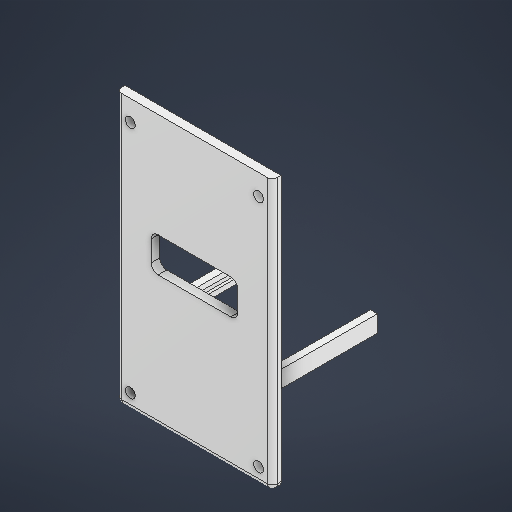
# Autodesk Inventor part: Крышка_голова_передняя
Saved by Autodesk Inventor 2026 (Build 300175050, 175E)
## iProperties
Created: 2026-10-25
Part Number: Крышка_голова_передняя
Material: Пластик АБС
Document SubType Name: Modeling
Designer: VK7
Density: 1.06 g/cm^3
Appearance: Гладкий — белый
Author: VK7
Autodesk Inventor part; units mm, degrees
ref_plane "YZ Plane" through (0, 0, 0) normal (1, 0, 0) x (0, 1, 0)
ref_plane "XZ Plane" through (0, 0, 0) normal (0, 1, 0) x (-1, 0, 0)
sketch "Эскиз1" plane through (0, 0, 0) normal (0, 0, 1) x (1, 0, 0)
  line L0 (0, 0) -> (45, 0)
  line L1 (45, 0) -> (45, 78)
  line L2 (45, 78) -> (0, 78)
  line L3 (0, 78) -> (0, 0)
  dimension "d0" = 45
  dimension "d1" = 78
  constraints: 8 end point, 2 parallel, 1 horizontal, 1 perpendicular
  measures "d0" distance of L2.end L1.end
  measures "d1" distance of L1.end L0.end
extrude "Выдавливание1" add sketch "Эскиз1" along normal blind 2.5
sketch "Эскиз2" plane through (0, 0, 2.5) normal (0, 0, 1) x (1, 0, 0)
  line L0 (0, 0) -> (4, 0)
  line L1 (0, 0) -> (45, 0) projected
  line L2 (4, 0) -> (4, 4.45)
  circle A0 centre (4, 4.45) radius 1.4
  line L3 (22.5, 0) -> (22.5, 4.5)
  circle A1 centre (41, 4.45) radius 1.4
  line L4 (4, 4.45) -> (4, 38.225)
  line L5 (4, 38.225) -> (6, 38.225)
  circle A2 centre (4, 72) radius 1.4
  circle A3 centre (41, 72) radius 1.4
  dimension "d4" = 4
  dimension "d5" = 4.45
  dimension "d6" = 2.8
  dimension "d36" = 33.775
  dimension "d37" = 2
  constraints: 10 end point, 4 centre point, 3 symmetric about line, 2 perpendicular, 2 vertical, 1 coincident, 1 midpoint, 1 point on line, 3 other
  measures "d4" distance of L0.start L0.end
  measures "d5" distance of L0.end L2.end
  measures "d6" diameter of A0
  measures "d36" distance of L4.start L4.end
  measures "d37" distance of L4.end L5.end
extrude "Выдавливание2" cut sketch "Эскиз2" against normal blind 2.5
ref_plane "РабПлоскость1" through (0, 21, 0) normal (0, -1, 0) x (1, 0, 0)
fillet "Сопряжение4" radius 1.5 3 edges at (0, 39, 2.5) (45, 39, 2.5) (22.5, 0, 2.5)
fillet "Сопряжение5" radius 1.5 4 edges at (44.5607, 0.4393, 2.0607) (45, 0, 0.5) (0, 0, 0.5) (0.4393, 0.4393, 2.0607)
sketch "Эскиз4" plane through (0, 0, 0) normal (0, 0, -1) x (-1, 0, 0)
  line L0 (-1.5, 0) -> (-43.5, 0) projected
  line L1 (-22.5, 0) -> (-22.5, 21)
  line L2 (-22.5, 21) -> (-22.5, 21.925)
  line L3 (-22.5, 21.925) -> (-38.6, 21.925)
  line L4 (-38.6, 21.925) -> (-38.6, 21)
  line L5 (-38.6, 21) -> (-37.8, 21)
  line L6 (-37.8, 21) -> (-37.8, 19.5)
  line L7 (-37.8, 19.5) -> (-39.8, 19.5)
  line L8 (-39.8, 19.5) -> (-39.8, 21.925)
  line L9 (-38.6, 21.925) -> (-38.6, 22.85)
  line L10 (-38.6, 22.85) -> (-37.8, 22.85)
  line L11 (-37.8, 22.85) -> (-37.8, 24.35)
  line L12 (-37.8, 24.35) -> (-39.8, 24.35)
  line L13 (-39.8, 24.35) -> (-39.8, 21.925)
  line L14 (-6.4, 21.925) -> (-6.4, 21)
  line L15 (-6.4, 21) -> (-7.2, 21)
  line L16 (-7.2, 21) -> (-7.2, 19.5)
  line L17 (-7.2, 19.5) -> (-5.2, 19.5)
  line L18 (-5.2, 19.5) -> (-5.2, 21.925)
  line L19 (-5.2, 24.35) -> (-5.2, 21.925)
  line L20 (-7.2, 24.35) -> (-5.2, 24.35)
  line L21 (-7.2, 22.85) -> (-7.2, 24.35)
  line L22 (-6.4, 22.85) -> (-7.2, 22.85)
  line L23 (-6.4, 21.925) -> (-6.4, 22.85)
  point P0 (0, 0)
  dimension "d27" = 21
  dimension "d28" = 0.925
  dimension "d29" = 16.1
  dimension "d30" = 0.8
  dimension "d31" = 1.5
  dimension "d32" = 2
  constraints: 46 end point, 14 symmetric about line, 5 perpendicular, 1 horizontal, 1 midpoint, 1 point on line, 1 vertical
  measures "d27" distance of L1.start L1.end
  measures "d28" distance of L1.end L2.end
  measures "d29" distance of L2.end L3.end
  measures "d30" distance of L4.end L5.end
  measures "d31" distance of L5.end L6.end
  measures "d32" distance of L6.end L7.end
extrude "Выдавливание4" add sketch "Эскиз4" along normal blind 33
fillet "Сопряжение7" radius 2 6 edges at (38.8, 19.5, 0) (39.8, 21.925, 0) (38.8, 24.35, 0) (6.2, 19.5, 0) (5.2, 21.925, 0) (6.2, 24.35, 0)
sketch "Эскиз6" plane through (0, 0, 0) normal (0, 0, -1) x (-1, 0, 0)
  line L0 (-1.5, 0) -> (-43.5, 0) projected
  line L1 (-22.5, 0) -> (-22.5, 42.9)
  line L2 (-35, 47.9) -> (-10, 47.9)
  line L3 (-10, 47.9) -> (-10, 37.9)
  line L4 (-10, 37.9) -> (-35, 37.9)
  line L5 (-35, 37.9) -> (-35, 47.9)
  line L6 (-35, 47.9) -> (-10, 37.9) construction
  line L7 (-10, 47.9) -> (-35, 37.9) construction
  point P0 (0, 0)
  dimension "d38" = 42.9
  dimension "d39" = 25
  dimension "d40" = 10
  constraints: 14 end point, 3 midpoint, 2 parallel, 1 horizontal, 1 perpendicular, 1 vertical
  measures "d38" distance of L1.start L1.end
  measures "d39" distance of L3.end L4.end
  measures "d40" distance of L2.end L3.end
extrude "Выдавливание5" cut sketch "Эскиз6" against normal blind 3
fillet "Сопряжение8" radius 2 4 edges at (35, 47.9, 1.25) (35, 37.9, 1.25) (10, 47.9, 1.25) (10, 37.9, 1.25)
